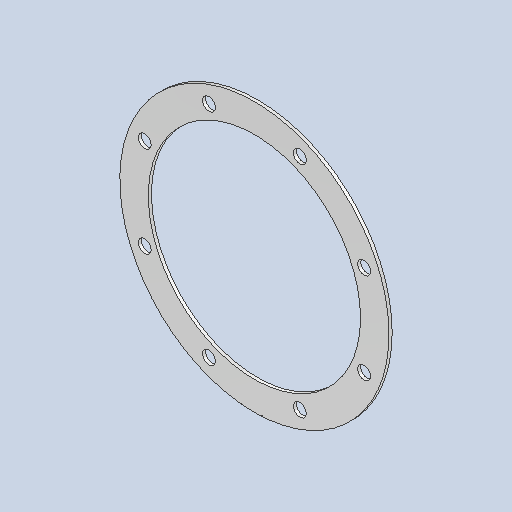
# Autodesk Inventor part: DMF-1614 Connector Ring
Saved by Autodesk Inventor 2026.2 (Build 302298000, 298)
## iProperties
Created: 2024-04-30
Part Number: DMF-1614 Connector Ring
Material: Stainless Steel AISI 304
Document SubType Name: Sheet Metal
Designer: admin
Stock Number: DMF-1614
Mass: 16.575 g
Surface Area: 188.37 cm^2
Volume: 16.575 cm^3
Density: 8 g/cm^3
Flat Pattern Width: 17 cm
Flat Pattern Length: 17 cm
Flat Pattern Area: 289 cm^2
Sheet Metal Rule: Default
Sheet Metal Width: 170,000 mm
Sheet Metal Length: 170,000 mm
Sheet Metal Area: 28900,000 mm^2
Appearance: Chrome - Satin
Author: pokla
Autodesk Inventor part; units mm, degrees
ref_plane "YZ Plane" through (0, 0, 0) normal (1, 0, 0) x (0, 1, 0)
ref_plane "XZ Plane" through (0, 0, 0) normal (0, 1, 0) x (-1, 0, 0)
ref_plane "XY Plane" through (0, 0, 0) normal (0, 0, 1) x (1, 0, 0)
sketch "Sketch1" plane through (0, 0, 0) normal (0, 0, 1) x (1, 0, 0)
  circle A0 centre (0, 0) radius 67
  circle A1 centre (0, 0) radius 85
  line L0 (0, 0) -> (0, 67) construction
  line L1 (0, 0) -> (-85, 0) construction
  circle A2 centre (28.7013, 69.291) radius 4.1
  line L2 (28.7013, 69.291) -> (0, 0) construction
  circle A3 centre (0, 0) radius 75 construction
  circle A4 centre (-28.7013, 69.291) radius 4.1
  circle A5 centre (-69.291, 28.7013) radius 4.1
  circle A6 centre (-69.291, -28.7013) radius 4.1
  circle A7 centre (-28.7013, -69.291) radius 4.1
  circle A8 centre (28.7013, -69.291) radius 4.1
  circle A9 centre (69.291, -28.7013) radius 4.1
  circle A10 centre (69.291, 28.7013) radius 4.1
  line L3 (-22.0961, -84.0028) -> (50.6342, -84.0028) construction
  line L4 (50.6342, -84.0028) -> (50.6342, -90.3599) construction
  line L5 (50.6342, -90.3599) -> (-22.0961, -90.3599) construction
  line L6 (-22.0961, -90.3599) -> (-22.0961, -84.0028) construction
  point P0 (0, -85)
  dimension "d32" = 134
  dimension "d97" = 150
  dimension "d31" = 170
  dimension "d95" = 8.2
  dimension "d96" = 22.5
  dimension "d100" = 360
  constraints: 9 centre point, 9 coincident, 6 end point, 2 point on circle, 2 vertical alignment, 1 horizontal, 1 vertical, 24 other
  measures "d31" diameter of A1
  measures "d95" diameter of A2
  measures "d96" angle of L2 L0
extrude "Plate4" add sketch "Sketch1" against normal blind 2
mark "Mark2"
equation "\"d63\" = Thickness"
equation "\"BendRadius\" = Thickness"
equation "\"BendReliefWidth\" = Thickness"
equation "\"BendReliefDepth\" = 0.5 * Thickness"
equation "\"CornerReliefSize\" = 4 * Thickness"
equation "\"MinimumRemnant\" = 2 * Thickness"
equation "\"TransitionRadius\" = BendRadius"
equation "\"JacobiRadiusSize\" = BendRadius"
equation "\"GapSize\" = Thickness"
equation "\"Thickness\" = 2"
body "Solid3"
